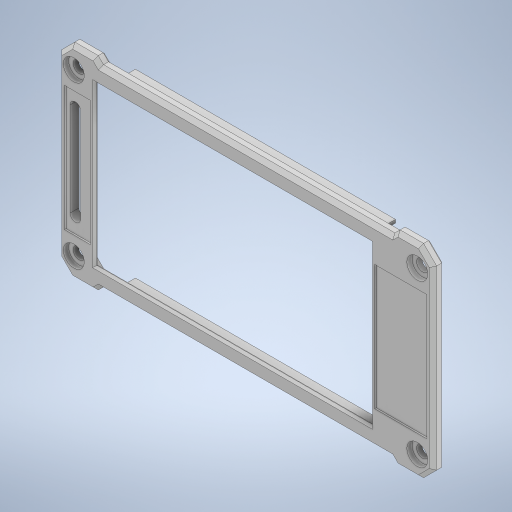
# Autodesk Inventor part: Cadre V3
Saved by Autodesk Inventor 2024 (Build 280153000, 153)
## iProperties
Created: 2026-10-31
Part Number: Cadre V3
Material: Générique
Document SubType Name: Modeling
Designer: berno
Density: 1 g/cm^3
Appearance: Par défaut
Author: berno
Autodesk Inventor part; units mm, degrees
sketch "Esq Cadre" plane through (0, 0, 0) normal (0, 0, 1) x (1, 0, 0)
  line L0 (72, -34) -> (72, 34)
  line L1 (72, 34) -> (67, 39)
  line L2 (67, 39) -> (58, 39)
  line L3 (58, 39) -> (56, 37)
  line L4 (56, 37) -> (-56, 37)
  line L5 (-56, 37) -> (-58, 39)
  line L6 (-58, 39) -> (-67, 39)
  line L7 (-67, 39) -> (-72, 34)
  line L8 (-72, 34) -> (-72, -34)
  line L9 (-72, -34) -> (-67, -39)
  line L10 (-67, -39) -> (-58, -39)
  line L11 (-58, -39) -> (-56, -37)
  line L12 (-56, -37) -> (56, -37)
  line L13 (56, -37) -> (58, -39)
  line L14 (58, -39) -> (67, -39)
  line L15 (67, -39) -> (72, -34)
  constraints: 32 end point
extrude "Cadre" add sketch "Esq Cadre" along normal blind 4
sketch "Esq Logement vitre" plane through (0, 0, 0) normal (0, 0, 1) x (1, 0, 0)
  line L0 (-61.5, -30.5) -> (-61.5, 30.5)
  line L1 (-61.5, 30.5) -> (-56.5, 35.5)
  line L2 (-56.5, 35.5) -> (56.5, 35.5)
  line L3 (56.5, 35.5) -> (61.5, 30.5)
  line L4 (61.5, 30.5) -> (61.5, -30.5)
  line L5 (61.5, -30.5) -> (56.5, -35.5)
  line L6 (56.5, -35.5) -> (-56.5, -35.5)
  line L7 (-56.5, -35.5) -> (-61.5, -30.5)
  constraints: 16 end point
extrude "Logement vitre" cut sketch "Esq Logement vitre" along normal blind 3
ref_plane "Plan de construction1" through (0, 0, 4) normal (0, 0, 1) x (1, 0, 0)
sketch "Esq Fenetre ecran" plane through (0, 0, 4) normal (0, 0, 1) x (1, 0, 0)
  line L0 (-58, -30.5) -> (48, -30.5)
  line L1 (48, -30.5) -> (48, 30.5)
  line L2 (48, 30.5) -> (-58, 30.5)
  line L3 (-58, 30.5) -> (-58, -30.5)
  constraints: 8 end point, 2 parallel, 1 horizontal, 1 perpendicular
extrude "Fenetre ecran" cut sketch "Esq Fenetre ecran" against normal blind 1.5
chamfer "Chanfrein avant" distance 1.4 angle 45 16 edges at (69.5, -36.5, 4) (62.5, -39, 4) (57, -38, 4) (0, -37, 4) (-57, -38, 4) (-62.5, -39, 4) (-69.5, -36.5, 4) (-72, 0, 4) (-69.5, 36.5, 4) (-62.5, 39, 4) (-57, 38, 4) (0, 37, 4) (57, 38, 4) (62.5, 39, 4) (69.5, 36.5, 4) (72, 0, 4)
chamfer "Chanfrein fenetre" distance 0.8 angle 45 4 edges at (48, 0, 4) (-5, -30.5, 4) (-58, 0, 4) (-5, 30.5, 4)
chamfer "Chanfrein logement" distance 1.4 angle 45 8 edges at (-59, 33, 3) (0, 35.5, 3) (59, 33, 3) (61.5, 0, 3) (59, -33, 3) (0, -35.5, 3) (-59, -33, 3) (-61.5, 0, 3)
ref_plane "Plan de construction2" through (0, 0, 4) normal (0, 0, 1) x (1, 0, 0)
sketch "Esq Creux haut et menton" plane through (0, 0, 4) normal (0, 0, 1) x (1, 0, 0)
  line L0 (-69.6, -24) -> (-59.6, -24)
  line L1 (-59.6, -24) -> (-59.6, 24)
  line L2 (-59.6, 24) -> (-69.6, 24)
  line L3 (-69.6, 24) -> (-69.6, -24)
  line L4 (49.6, -24) -> (69.6, -24)
  line L5 (69.6, -24) -> (69.6, 24)
  line L6 (69.6, 24) -> (49.6, 24)
  line L7 (49.6, 24) -> (49.6, -24)
  constraints: 16 end point, 4 parallel, 2 horizontal, 2 perpendicular
extrude "Creux haut et menton" cut sketch "Esq Creux haut et menton" against normal blind 0.6
ref_plane "Plan de construction3" through (0, 0, 4) normal (0, 0, 1) x (1, 0, 0)
sketch "Esq Trous vis M4" plane through (0, 0, 4) normal (0, 0, 1) x (1, 0, 0)
  circle A0 centre (66, 31) radius 2.25
  circle A1 centre (66, -31) radius 2.25
  circle A2 centre (-66, 31) radius 2.25
  circle A3 centre (-66, -31) radius 2.25
  constraints: 4 centre point
extrude "Trous vis M4" cut sketch "Esq Trous vis M4" against normal blind 5
ref_plane "Plan de construction4" through (0, 0, 4) normal (0, 0, 1) x (1, 0, 0)
sketch "Esq Lamages vis" plane through (0, 0, 4) normal (0, 0, 1) x (1, 0, 0)
  circle A0 centre (66, 31) radius 4
  circle A1 centre (66, -31) radius 4
  circle A2 centre (-66, 31) radius 4
  circle A3 centre (-66, -31) radius 4
  constraints: 4 centre point
extrude "Lamages vis" cut sketch "Esq Lamages vis" against normal blind 2
sketch "Esq Passant dragonne" plane through (0, 0, 0) normal (0, 0, 1) x (1, 0, 0)
  line L0 (-64, -18) -> (-64, 18)
  line L1 (-68, 18) -> (-68, -18)
  arc A0 (-64, 18) -> (-68, 18) centre (-66, 18) ccw
  arc A1 (-68, -18) -> (-64, -18) centre (-66, -18) ccw
  constraints: 4 end point, 4 point on circle, 2 centre point
extrude "Passant dragonne" cut sketch "Esq Passant dragonne" along normal blind 5
sketch "Esq Languette" plane through (0, 0, 0) normal (0, 0, 1) x (1, 0, 0)
  line L0 (-50, 34.15) -> (50, 34.15)
  line L1 (50, 34.15) -> (50, 35.35)
  line L2 (50, 35.35) -> (-50, 35.35)
  line L3 (-50, 35.35) -> (-50, 34.15)
  line L4 (-50, -35.35) -> (50, -35.35)
  line L5 (50, -35.35) -> (50, -34.15)
  line L6 (50, -34.15) -> (-50, -34.15)
  line L7 (-50, -34.15) -> (-50, -35.35)
  constraints: 16 end point, 4 parallel, 2 horizontal, 2 perpendicular
extrude "Languette" add sketch "Esq Languette" against normal blind 4
sketch "Esq Liaison languette" plane through (0, 0, 0) normal (0, 0, 1) x (1, 0, 0)
  line L0 (-50, 34.15) -> (50, 34.15)
  line L1 (50, 34.15) -> (50, 36)
  line L2 (50, 36) -> (-50, 36)
  line L3 (-50, 36) -> (-50, 34.15)
  line L4 (-50, -36) -> (50, -36)
  line L5 (50, -36) -> (50, -34.15)
  line L6 (50, -34.15) -> (-50, -34.15)
  line L7 (-50, -34.15) -> (-50, -36)
  constraints: 16 end point, 4 parallel, 2 horizontal, 2 perpendicular
extrude "Liaison languette" add sketch "Esq Liaison languette" along normal blind 1.6
chamfer "Chanfrein languette" distance 0.35 angle 45 8 edges at (0, 34.15, -4) (-50, 34.75, -4) (0, 35.35, -4) (50, 34.75, -4) (0, -35.35, -4) (-50, -34.75, -4) (0, -34.15, -4) (50, -34.75, -4)
sketch "Esq Ligne d'ombre" plane through (0, 0, 0) normal (0, 0, 1) x (1, 0, 0)
  line L0 (-80, -45) -> (80, -45)
  line L1 (80, -45) -> (80, 45)
  line L2 (80, 45) -> (-80, 45)
  line L3 (-80, 45) -> (-80, -45)
  line L4 (71.3, -33.71) -> (66.71, -38.3)
  line L5 (66.71, -38.3) -> (58.29, -38.3)
  line L6 (58.29, -38.3) -> (56.29, -36.3)
  line L7 (56.29, -36.3) -> (-56.29, -36.3)
  line L8 (-56.29, -36.3) -> (-58.29, -38.3)
  line L9 (-58.29, -38.3) -> (-66.71, -38.3)
  line L10 (-66.71, -38.3) -> (-71.3, -33.71)
  line L11 (-71.3, -33.71) -> (-71.3, 33.71)
  line L12 (-71.3, 33.71) -> (-66.71, 38.3)
  line L13 (-66.71, 38.3) -> (-58.29, 38.3)
  line L14 (-58.29, 38.3) -> (-56.29, 36.3)
  line L15 (-56.29, 36.3) -> (56.29, 36.3)
  line L16 (56.29, 36.3) -> (58.29, 38.3)
  line L17 (58.29, 38.3) -> (66.71, 38.3)
  line L18 (66.71, 38.3) -> (71.3, 33.71)
  line L19 (71.3, 33.71) -> (71.3, -33.71)
  constraints: 40 end point, 2 parallel, 1 horizontal, 1 perpendicular
extrude "Ligne d'ombre" cut sketch "Esq Ligne d'ombre" along normal blind 0.7
